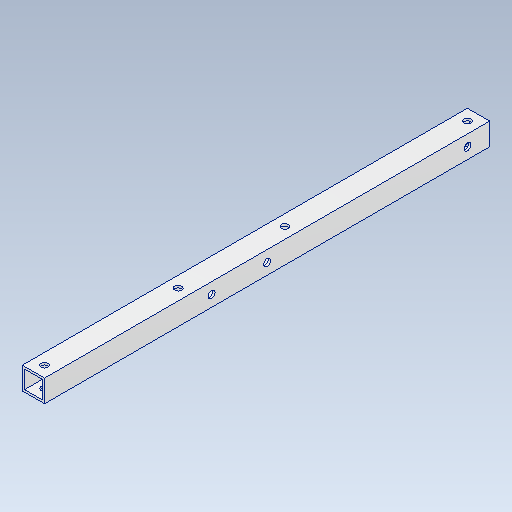
# Autodesk Inventor part: alsp_10_10_200_1
Saved by Autodesk Inventor 2027.1 (Build 311270010, 270A)
## iProperties
Created: 2026-10-20
Part Number: alsp_10_10_200_1
Material: アルミニウム 6061
Document SubType Name: Modeling
Designer: ug_nd
Density: 2.7 g/cm^3
Appearance: アルミニウム - フラット
Author: ug_nd
Autodesk Inventor part; units mm, degrees
ref_plane "YZ Plane" through (0, 0, 0) normal (1, 0, 0) x (0, 1, 0)
ref_plane "XZ Plane" through (0, 0, 0) normal (0, 1, 0) x (-1, 0, 0)
ref_plane "XY Plane" through (0, 0, 0) normal (0, 0, 1) x (1, 0, 0)
sketch "スケッチ1" plane through (0, 0, 0) normal (0, 0, 1) x (1, 0, 0)
  line L0 (-5, -5) -> (5, -5)
  line L1 (5, -5) -> (5, 5)
  line L2 (5, 5) -> (-5, 5)
  line L3 (-5, 5) -> (-5, -5)
  line L4 (-5, -5) -> (5, 5) construction
  line L5 (5, -5) -> (-5, 5) construction
  line L6 (-4, -4) -> (4, -4)
  line L7 (4, -4) -> (4, 4)
  line L8 (4, 4) -> (-4, 4)
  line L9 (-4, 4) -> (-4, -4)
  line L10 (-4, -4) -> (4, 4) construction
  line L11 (4, -4) -> (-4, 4) construction
  point P0 (0, 0)
  dimension "d0" = 10
  dimension "d1" = 10
  dimension "d2" = 1
  dimension "d3" = 1
  constraints: 24 end point, 4 midpoint, 4 parallel, 2 horizontal, 2 perpendicular
  measures "d0" distance of L1.end L2.end
  measures "d1" distance of L2.end L0.start
  measures "d2" distance between parallel lines of L8 L2
  measures "d3" distance between parallel lines of L3 L9
extrude "押し出し1" add sketch "スケッチ1" along normal mid plane 200
sketch "スケッチ2" plane through (-5, 5, 100) normal (0, 1, 0) x (1, 0, 0)
  line L0 (5, 240) -> (5, -40) construction
  line L1 (10, 0) -> (0, 0) construction
  circle A0 centre (5, 5) radius 1.6
  circle A1 centre (5, 65) radius 1.6
  circle A2 centre (5, 195) radius 1.6
  circle A3 centre (5, 113) radius 1.6
  point P0 (5, 100)
  dimension "d6" = 5
  dimension "d7" = 60
  dimension "d8" = 3.2
  dimension "d17" = 190
  dimension "d18" = 113
  constraints: 4 centre point, 4 point on line, 3 equal radius
  measures "d6" distance from line of L1 A0.centre
  measures "d7" distance of A1.centre A0.centre
  measures "d8" diameter of A0
  measures "d17" distance of A0.centre A2.centre
  measures "d18" distance from line of L1 A3.centre
extrude "押し出し2" cut sketch "スケッチ2" against normal through all
sketch "スケッチ3" plane through (5, -5, 100) normal (1, 0, 0) x (0, 0, -1)
  line L0 (240, 5) -> (-40, 5) construction
  line L1 (0, 0) -> (0, 10) construction
  circle A0 centre (75, 5) radius 1.6
  circle A1 centre (100, 5) radius 1.6
  circle A2 centre (190, 5) radius 1.6
  dimension "d11" = 3.2
  dimension "d12" = 75
  dimension "d13" = 25
  dimension "d14" = 190
  constraints: 3 centre point, 2 equal radius, 2 point on line, 1 midpoint
  measures "d11" diameter of A0
  measures "d12" distance from line of L1 A0.centre
  measures "d13" distance of A1.centre A0.centre
  measures "d14" distance from line of L1 A2.centre
extrude "押し出し3" cut sketch "スケッチ3" against normal through all
